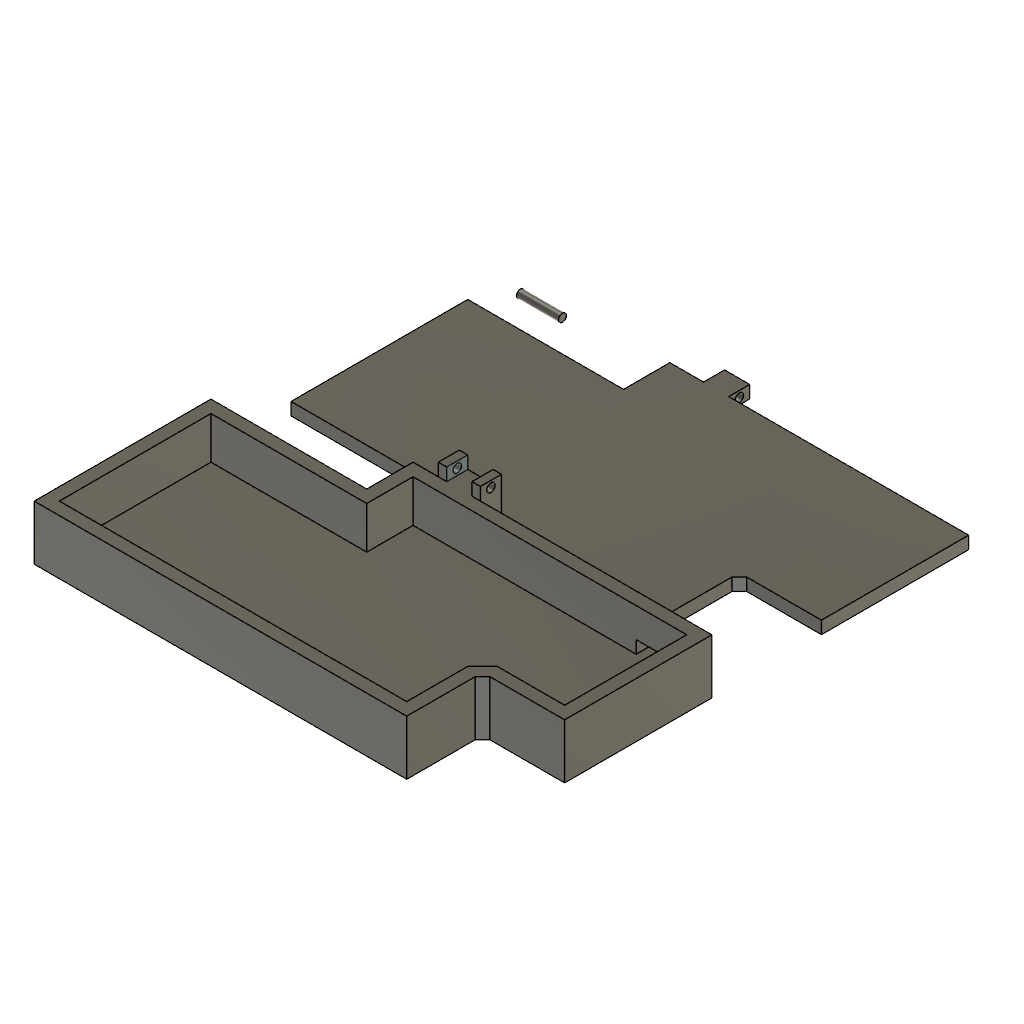
Lumen Ring Case (Autodesk Fusion 360 design; units mm, degrees)
part number: 2026-11-01-20-10-35-422
Autodesk Fusion 360 part; units mm, degrees
sketch "Sketch1" plane through (0, 0, 0) normal (0, 0, 1) x (1, 0, 0)
  line L0 (0, 0) -> (82.5, 0)
  line L1 (102, 18) -> (102, 47)
  line L2 (102, 47) -> (37, 47)
  line L3 (0, 36) -> (0, 0)
  line L4 (37, 47) -> (37, 36)
  line L5 (37, 36) -> (0, 36)
  line L6 (86, 18) -> (102, 18)
  line L7 (82.5, 0) -> (82.5, 14.5)
  line L8 (86, 18) -> (82.5, 14.5)
  line L9 (-3, -3) -> (85.5, -3)
  line L10 (85.5, -3) -> (85.5, 13.2574)
  line L11 (87.2426, 15) -> (85.5, 13.2574)
  line L12 (87.2426, 15) -> (105, 15)
  line L13 (105, 15) -> (105, 50)
  line L14 (105, 50) -> (34, 50)
  line L15 (34, 50) -> (34, 39)
  line L16 (34, 39) -> (-3, 39)
  line L17 (-3, 39) -> (-3, -3)
  dimension "d9" = 3
  constraint horizontal L0
  constraint vertical L1
  constraint horizontal L2
  constraint vertical L3
  constraint coincident L0.start L3.end
  constraint vertical L4
  constraint horizontal L5
  constraint horizontal L6
  constraint vertical L7
extrude "Extrude1" add sketch "Sketch1" along normal blind 13 makes body 1
sketch "Sketch2" plane through (0, 0, 0) normal (0, 0, 1) x (1, 0, 0)
  line L0 (37, 47) -> (102, 47)
  line L1 (102, 47) -> (102, 18)
  line L2 (102, 18) -> (86, 18)
  line L3 (86, 18) -> (82.5, 14.5)
  line L4 (82.5, 14.5) -> (82.5, 0)
  line L5 (82.5, 0) -> (0, 0)
  line L6 (0, 0) -> (0, 36)
  line L7 (0, 36) -> (37, 36)
  line L8 (37, 36) -> (37, 47)
  constraint horizontal L0
  constraint perpendicular L0 L1
  constraint perpendicular L1 L2
  constraint perpendicular L2 L4
  constraint coincident L5.end L6.start
  constraint perpendicular L4 L5
  constraint perpendicular L5 L6
  constraint perpendicular L4 L7
  constraint perpendicular L0 L8
extrude "Extrude2" add sketch "Sketch2" along normal blind 3 bodies 1
sketch "Sketch3" plane through (0, 50, 0) normal (0, 1, 0) x (-1, 0, 0)
  line L0 (-105, 0) -> (-34, 0)
  line L1 (-34, 0) -> (-34, 13)
  line L2 (-34, 13) -> (-105, 13)
  line L3 (-105, 13) -> (-105, 0)
  line L4 (-100, 0) -> (-100, 3)
  line L5 (-105, 3) -> (-100, 3)
  line L6 (-100, 3) -> (-90, 3)
  line L7 (-90, 3) -> (-90, 6)
  line L8 (-90, 6) -> (-100, 6)
  line L9 (-100, 6) -> (-100, 3)
  constraint coincident L0 L4.start
  constraint perpendicular L0 L4
  constraint coincident L3 L5.start
  constraint perpendicular L4 L5
  constraint horizontal L6
  constraint vertical L7
  constraint horizontal L8
  constraint vertical L9
extrude "Extrude3" cut sketch "Sketch3" against normal blind 16 contours L6 L7 L8 L9 bodies 1
sketch "Sketch4" plane through (0, 0, 13) normal (0, 0, 1) x (-1, 0, 0)
  line L0 (-102, -47) -> (-102, -18)
  line L1 (-102, -18) -> (-86, -18)
  line L2 (-86, -18) -> (-82.5, -14.5)
  line L3 (-82.5, -14.5) -> (-82.5, 0)
  line L4 (-82.5, 0) -> (0, 0)
  line L5 (0, 0) -> (0, -36)
  line L6 (0, -36) -> (-37, -36)
  line L7 (-37, -36) -> (-37, -47)
  line L8 (-37, -47) -> (-102, -47)
  line L9 (-87.2426, -15) -> (-105, -15)
  line L10 (-105, -15) -> (-105, -50)
  line L11 (-105, -50) -> (-34, -50)
  line L12 (-34, -50) -> (-34, -39)
  line L13 (-34, -39) -> (3, -39)
  line L14 (3, -39) -> (3, 3)
  line L15 (3, 3) -> (-85.5, 3)
  line L16 (-85.5, 3) -> (-85.5, -13.2574)
  line L17 (-85.5, -13.2574) -> (-87.2426, -15)
  line L18 (-34, -50) -> (-34, -39)
  line L19 (-34, -39) -> (3, -39)
  line L20 (3, -39) -> (3, 3)
  line L21 (3, 3) -> (-85.5, 3)
  line L22 (-85.5, 3) -> (-85.5, -13.2574)
  line L23 (-85.5, -13.2574) -> (-87.2426, -15)
  line L24 (-87.2426, -15) -> (-105, -15)
  line L25 (-105, -15) -> (-105, -50)
  line L26 (-105, -50) -> (-34, -50)
  constraint coincident L11.end L12.start
  constraint coincident L12.end L13.start
  constraint coincident L13.end L14.start
  constraint coincident L14.end L15.start
  constraint coincident L15.end L16.start
  constraint coincident L16.end L17.start
  constraint coincident L9.start L17.end
  constraint coincident L9.end L10.start
  constraint coincident L10.end L11.start
extrude "Extrude4" add sketch "Sketch4" along normal blind 3 separate body contours L0 L1 L2 L3 L4 L5 L6 L7 L8 | L9 L10 L11 L12 L13 L14 L15 L16 L17 L18 L19 L20 L21 L22 L23 L24 L25 L26 makes body 2
move_body "Move1" bodies 2 to x (1, 0, 0) y (0, 1, 0) z (0, 0, 1) at (0, 61, -13)
sketch "Sketch5" plane through (0, 50, 0) normal (0, 1, 0) x (-1, 0, 0)
  line L0 (-90, 3) -> (-100, 3)
  line L1 (-100, 3) -> (-100, 6)
  line L2 (-100, 6) -> (-90, 6)
  line L3 (-90, 6) -> (-90, 3)
  line L4 (-105, 0) -> (-34, 0)
  line L5 (-34, 0) -> (-34, 13)
  line L6 (-34, 13) -> (-105, 13)
  line L7 (-105, 13) -> (-105, 0)
  line L8 (-40, 13) -> (-50, 13)
  line L9 (-50, 13) -> (-50, 10)
  line L10 (-50, 10) -> (-50, 8)
  line L11 (-50, 8) -> (-40, 8)
  line L12 (-40, 8) -> (-40, 13)
  constraint coincident L6 L8.start
  constraint coincident L6 L8.end
  constraint perpendicular L6 L9
  constraint perpendicular L6 L10
  constraint perpendicular L10 L11
  constraint perpendicular L6 L12
extrude "Extrude5" add sketch "Sketch5" along normal blind 5 contours L6 L8 L9 L10 L11 L12 bodies 1
sketch "Sketch6" plane through (0, 0, 13) normal (0, 0, 1) x (-1, 0, 0)
  line L0 (-102, -47) -> (-102, -18)
  line L1 (-102, -18) -> (-86, -18)
  line L2 (-86, -18) -> (-82.5, -14.5)
  line L3 (-82.5, -14.5) -> (-82.5, 0)
  line L4 (-82.5, 0) -> (0, 0)
  line L5 (0, 0) -> (0, -36)
  line L6 (0, -36) -> (-37, -36)
  line L7 (-37, -36) -> (-37, -47)
  line L8 (-37, -47) -> (-102, -47)
  line L9 (-87.2426, -15) -> (-105, -15)
  line L10 (-105, -15) -> (-105, -50)
  line L11 (-105, -50) -> (-50, -50)
  line L12 (-50, -50) -> (-50, -55)
  line L13 (-50, -55) -> (-40, -55)
  line L14 (-40, -55) -> (-40, -50)
  line L15 (-40, -50) -> (-34, -50)
  line L16 (-34, -50) -> (-34, -39)
  line L17 (-34, -39) -> (3, -39)
  line L18 (3, -39) -> (3, 3)
  line L19 (3, 3) -> (-85.5, 3)
  line L20 (-85.5, 3) -> (-85.5, -13.2574)
  line L21 (-85.5, -13.2574) -> (-87.2426, -15)
  line L22 (-48, -55) -> (-50, -55)
  line L23 (-50, -55) -> (-50, -50)
  line L24 (-50, -50) -> (-48, -50)
  line L25 (-48, -50) -> (-48, -55)
  line L26 (-40, -50) -> (-42, -50)
  line L27 (-42, -50) -> (-42, -55)
  line L28 (-42, -55) -> (-40, -55)
  line L29 (-40, -55) -> (-40, -50)
  constraint horizontal L22
  constraint vertical L23
  constraint horizontal L24
  constraint vertical L25
  constraint coincident L11.end L12.start
  constraint coincident L13 L22.start
  constraint horizontal L26
  constraint vertical L27
  constraint horizontal L28
  constraint vertical L29
  constraint coincident L13 L27.end
  constraint coincident L14.end L15.start
extrude "Extrude6" add sketch "Sketch6" along normal blind 3 contours L12 L13 L22 L23 L24 L25 | L13 L14 L26 L27 L28 L29 bodies 1
sketch "Sketch7" plane through (50, 0, 0) normal (1, 0, 0) x (0, 1, 0)
  line L0 (50, 13) -> (50, 8)
  line L1 (50, 8) -> (55, 8)
  line L2 (55, 8) -> (55, 16)
  line L3 (55, 16) -> (50, 16)
  line L4 (50, 16) -> (50, 13)
  circle A0 centre (52.5, 14.5) radius 1
extrude "Extrude7" cut sketch "Sketch7" against normal blind 13 contours A0 bodies 1
sketch "Sketch8" plane through (0, 111, 0) normal (0, 1, 0) x (-1, 0, 0)
  line L0 (-105, 0) -> (-34, 0)
  line L1 (-34, 0) -> (-34, 3)
  line L2 (-34, 3) -> (-105, 3)
  line L3 (-105, 3) -> (-105, 0)
  line L4 (-40, 3) -> (-50, 3)
  line L5 (-50, 3) -> (-48, 3)
  line L6 (-48, 3) -> (-48, 0)
  line L7 (-48, 0) -> (-42, 0)
  line L8 (-42, 0) -> (-42, 3)
  constraint coincident L2 L4.start
  constraint coincident L2 L4.end
  constraint coincident L2 L5.end
  constraint perpendicular L2 L6
  constraint coincident L0 L7.end
  constraint perpendicular L6 L7
  constraint perpendicular L7 L8
extrude "Extrude8" add sketch "Sketch8" along normal blind 5 contours L0 L2 L4 L6 L7 L8 bodies 2
sketch "Sketch9" plane through (42, 0, 0) normal (1, 0, 0) x (0, 1, 0)
  circle A0 centre (52.5, 14.5) radius 1
  line L0 (50, 13) -> (55, 13)
  line L1 (55, 13) -> (55, 16)
  line L2 (55, 16) -> (50, 16)
  line L3 (50, 16) -> (50, 13)
sketch "Sketch10" plane through (48, 0, 0) normal (1, 0, 0) x (0, 1, 0)
  line L0 (111, 3) -> (111, 0)
  line L1 (111, 0) -> (116, 0)
  line L2 (116, 0) -> (116, 3)
  line L3 (116, 3) -> (111, 3)
  circle A0 centre (113.5, 1.5) radius 1
extrude "Extrude9" cut sketch "Sketch10" against normal blind 8.1 contours A0 bodies 2
sketch "Sketch11" plane through (0, 0, 0) normal (1, 0, 0) x (0, 1, 0)
  circle A0 centre (121.5, 0.95) radius 0.95
extrude "Extrude10" add sketch "Sketch11" along normal blind 10 separate body makes body 3
move_body "Move2" bodies 3 to x (1, 0, 0) y (0, 1, 0) z (0, 0, 1) at (0, -12, 0)
